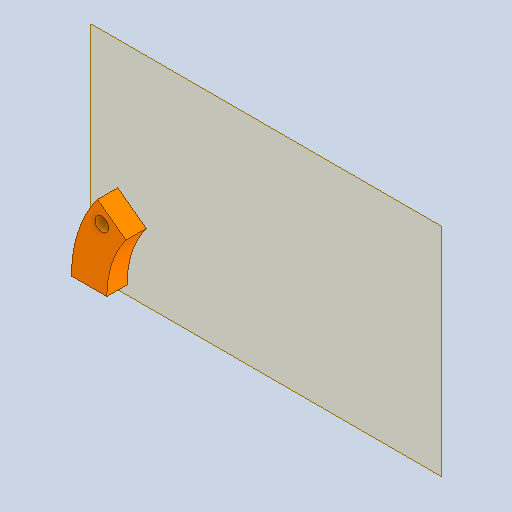
# Autodesk Inventor part: упормоторов
Saved by Autodesk Inventor 2024.2 (Build 282272000, 272)
## iProperties
Created: 2026-09-16
Part Number: упормоторов
Material: PLA
Document SubType Name: Modeling
Designer: katya_notebook
Density: 1.24 g/cm^3
Appearance: Типовые
Author: katya_notebook
Autodesk Inventor part; units mm, degrees
ref_plane "YZ Plane" through (0, 0, 0) normal (1, 0, 0) x (0, 1, 0)
ref_plane "XZ Plane" through (0, 0, 0) normal (0, 1, 0) x (-1, 0, 0)
ref_plane "XY Plane" through (0, 0, 0) normal (0, 0, 1) x (1, 0, 0)
ref_plane "РабПлоскость1" through (7.995, 0.1831, 0) normal (0, 0, 1) x (1, 0, 0)
sketch "Эскиз1" plane through (7.995, 0.1831, 0) normal (0, 0, 1) x (1, 0, 0)
  arc A0 (4.005, -0.1831) -> (43.005, -0.1831) centre (23.505, -0.1831) ccw projected
  circle A1 centre (23.505, -0.1831) radius 19.5
  circle A2 centre (23.505, -0.1831) radius 26.5
  line L0 (4.005, -0.1831) -> (-2.995, -0.1831)
  line L1 (23.505, -0.1831) -> (2.1466, 15.5035)
  circle A3 centre (3.0081, 11.7329) radius 1.35 projected
  point P0 (-7.995, -0.1831)
  point P1 (7.7885, 11.3599)
  dimension "d0" = 7
  constraints: 4 end point, 2 coincident, 2 point on circle, 1 centre point, 1 horizontal, 3 other
extrude "Выдавливание1" add sketch "Эскиз1" along normal blind 4 contours L0 A2 L1 A1
